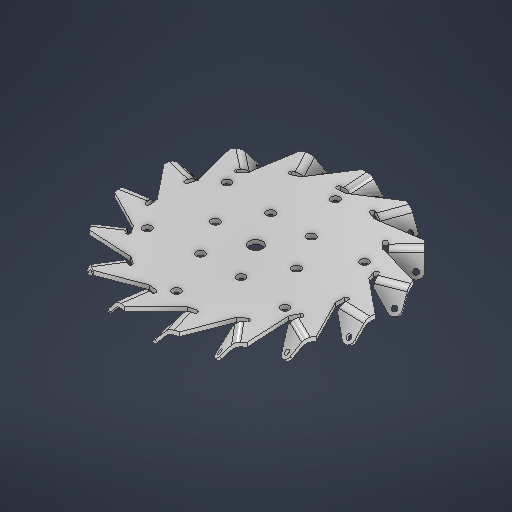
# Autodesk Inventor part: Pelk
Saved by Autodesk Inventor 2026.2 (Build 302298010, 298A)
## iProperties
Created: 2026-11-18
Part Number: Pelk
Material: Generic
Document SubType Name: Modeling
Designer: Administrator
Density: 1 g/cm^3
Appearance: Machined - Aluminum
Author: Administrator
Autodesk Inventor part; units mm, degrees
ref_plane "YZ Plane" through (0, 0, 0) normal (1, 0, 0) x (0, 1, 0)
ref_plane "XZ Plane" through (0, 0, 0) normal (0, 1, 0) x (-1, 0, 0)
sketch "Sketch1" plane through (0, 0, 0) normal (0, 1, 0) x (-1, 0, 0)
  circle A0 centre (0, 0) radius 70.5 construction
  circle A1 centre (0, 0) radius 28
  circle A2 centre (24, 0) radius 2.5
  circle A3 centre (0, -47) radius 2.5
  line L0 (-28, 0) -> (28, 0) construction
  line L1 (0, 53) -> (0, -53) construction
  circle A4 centre (12, 20.7846) radius 2.5
  circle A5 centre (40.7032, -23.5) radius 2.5
  circle A6 centre (-12, 20.7846) radius 2.5
  circle A7 centre (40.7032, 23.5) radius 2.5
  circle A8 centre (-24, 0) radius 2.5
  circle A9 centre (0, 47) radius 2.5
  circle A10 centre (-12, -20.7846) radius 2.5
  circle A11 centre (-40.7032, 23.5) radius 2.5
  circle A12 centre (12, -20.7846) radius 2.5
  circle A13 centre (-40.7032, -23.5) radius 2.5
  arc A14 (5.1152, -55.2638) -> (5.0796, -52.7716) centre (5, -54.0191) ccw
  line L2 (0, 0) -> (35.25, -61.0548) construction
  line L3 (68.9594, -14.6578) -> (52.7013, 5.6191)
  line L4 (68.9594, -14.6578) -> (67.7471, -19.5086)
  line L5 (67.7471, -19.5086) -> (53.3328, -15.3578)
  arc A15 (27.1508, -48.4054) -> (26.1046, -46.1432) centre (26.5393, -47.3152) ccw
  line L6 (0, 0) -> (57.0357, -41.4389) construction
  arc A16 (44.4917, -33.1773) -> (42.6159, -31.5363) centre (43.4897, -32.4301) ccw
  line L7 (0, 0) -> (68.9594, -14.6578) construction
  arc A17 (54.1397, -12.2126) -> (51.7585, -11.4764) centre (52.9203, -11.9375) ccw
  line L8 (0, 0) -> (68.9594, 14.6578) construction
  arc A18 (54.4263, 10.8638) -> (51.9516, 10.5679) centre (53.2005, 10.6191) ccw
  line L9 (0, 0) -> (57.0357, 41.4389) construction
  arc A19 (45.3022, 32.0618) -> (43.1618, 30.7849) centre (44.2819, 31.3397) ccw
  line L10 (0, 0) -> (35.25, 61.0548) construction
  arc A20 (28.3449, 47.716) -> (26.9089, 45.6788) centre (27.7065, 46.6413) ccw
  line L11 (0, 0) -> (7.3693, 70.1138) construction
  arc A21 (6.4866, 55.1196) -> (6.0033, 52.6745) centre (6.3405, 53.8782) ccw
  line L12 (0, 0) -> (-21.7857, 67.0495) construction
  arc A22 (-16.4934, 52.9926) -> (-15.9404, 50.5623) centre (-16.1219, 51.7991) ccw
  line L13 (0, 0) -> (-47.1737, 52.3917) construction
  arc A23 (-36.6215, 41.7027) -> (-35.1278, 39.7074) centre (-35.7967, 40.7634) ccw
  line L14 (0, 0) -> (-64.405, 28.6749) construction
  arc A24 (-50.4174, 23.202) -> (-48.2414, 21.9868) centre (-49.2819, 22.6794) ccw
  line L15 (0, 0) -> (-70.5, 0) construction
  arc A25 (-55.4957, 0.6895) -> (-53.0135, 0.4644) centre (-54.2458, 0.6739) ccw
  line L16 (0, 0) -> (-64.405, -28.6749) construction
  arc A26 (-50.9783, -21.9423) -> (-48.6191, -21.1383) centre (-49.8301, -21.4481) ccw
  line L17 (0, 0) -> (-47.1737, -52.3917) construction
  arc A27 (-37.6462, -40.78) -> (-35.8181, -39.086) centre (-36.7984, -39.8616) ccw
  line L18 (0, 0) -> (-21.7857, -67.0495) construction
  arc A28 (-17.8048, -52.5665) -> (-16.8237, -50.2753) centre (-17.4038, -51.3826) ccw
  line L19 (0, 0) -> (7.3693, -70.1138) construction
  line L20 (69.8249, 9.7332) -> (54.9685, 7.6623)
  line L21 (68.9594, 14.6578) -> (45.8595, 26.5689)
  line L22 (59.8293, 37.2921) -> (47.0997, 29.3576)
  line L23 (57.0357, 41.4389) -> (31.0882, 42.9246)
  line L24 (39.4888, 58.4028) -> (31.0869, 45.9767)
  line L25 (35.25, 61.0548) -> (10.9415, 51.8583)
  line L26 (12.3202, 69.4151) -> (9.6989, 54.646)
  line L27 (7.3693, 70.1138) -> (-11.0971, 51.8252)
  line L28 (-16.9786, 68.425) -> (-13.3661, 53.8665)
  line L29 (-21.7857, 67.0495) -> (-31.217, 42.8311)
  line L30 (-43.3417, 55.6035) -> (-34.12, 43.773)
  line L31 (-47.1737, 52.3917) -> (-45.9391, 26.4311)
  line L32 (-62.2106, 33.1677) -> (-48.9743, 26.1107)
  line L33 (-64.405, 28.6749) -> (-52.7179, 5.4609)
  line L34 (-70.3227, 4.9969) -> (-55.3604, 3.9337)
  line L35 (-70.5, 0) -> (-50.3813, -16.4536)
  line L36 (-66.2754, -24.038) -> (-52.1742, -18.9235)
  line L37 (-64.405, -28.6749) -> (-39.3334, -35.523)
  line L38 (-50.7685, -48.9164) -> (-39.9667, -38.5087)
  line L39 (-47.1737, -52.3917) -> (-21.4843, -48.4502)
  line L40 (-26.4832, -65.3367) -> (-20.8485, -51.4353)
  line L41 (-21.7857, -67.0495) -> (0.0796, -52.9999)
  line L42 (2.3812, -70.4598) -> (1.8746, -55.4683)
  line L43 (7.3693, -70.1138) -> (21.6297, -48.3855)
  line L44 (30.8339, -63.3997) -> (24.2735, -49.9104)
  line L45 (35.25, -61.0548) -> (39.4399, -35.4047)
  line L46 (53.9552, -45.3772) -> (42.4754, -35.7225)
  line L47 (57.0357, -41.4389) -> (50.4305, -16.3022)
  arc A29 (43.1618, 30.7849) -> (42.8905, 31.1617) centre (0, 0) ccw
  arc A30 (26.9089, 45.6788) -> (26.5078, 45.9128) centre (0, 0) ccw
  arc A31 (6.0033, 52.6745) -> (5.5416, 52.7251) centre (0, 0) ccw
  arc A32 (-15.9404, 50.5623) -> (-16.3827, 50.4208) centre (0, 0) ccw
  arc A33 (-35.1278, 39.7074) -> (-35.4743, 39.3982) centre (0, 0) ccw
  arc A34 (-48.2414, 21.9868) -> (-48.4321, 21.5634) centre (0, 0) ccw
  arc A35 (-53.0135, 0.4644) -> (-53.0155, 0) centre (0, 0) ccw
  arc A36 (-48.6191, -21.1383) -> (-48.4321, -21.5634) centre (0, 0) ccw
  arc A37 (-35.8181, -39.086) -> (-35.4743, -39.3982) centre (0, 0) ccw
  arc A38 (-16.8237, -50.2753) -> (-16.3827, -50.4208) centre (0, 0) ccw
  line L48 (68.9594, 14.6578) -> (69.8249, 9.7332)
  line L49 (57.0357, 41.4389) -> (59.8293, 37.2921)
  line L50 (35.25, 61.0548) -> (39.4888, 58.4028)
  line L51 (7.3693, 70.1138) -> (12.3202, 69.4151)
  line L52 (-21.7857, 67.0495) -> (-16.9786, 68.425)
  line L53 (-47.1737, 52.3917) -> (-43.3417, 55.6035)
  line L54 (-64.405, 28.6749) -> (-62.2106, 33.1677)
  line L55 (-70.5, 0) -> (-70.3227, 4.9969)
  line L56 (-64.405, -28.6749) -> (-66.2754, -24.038)
  line L57 (-47.1737, -52.3917) -> (-50.7685, -48.9164)
  line L58 (-21.7857, -67.0495) -> (-26.4832, -65.3367)
  line L59 (7.3693, -70.1138) -> (2.3812, -70.4598)
  line L60 (35.25, -61.0548) -> (30.8339, -63.3997)
  line L61 (57.0357, -41.4389) -> (53.9552, -45.3772)
  line L62 (5.0796, -52.7716) -> (0.0796, -52.9999)
  line L63 (5.1152, -55.2638) -> (1.8746, -55.4683)
  line L64 (26.1046, -46.1432) -> (21.6297, -48.3855)
  line L65 (27.1508, -48.4054) -> (24.2735, -49.9104)
  line L66 (42.6159, -31.5363) -> (39.4399, -35.4047)
  line L67 (44.4917, -33.1773) -> (42.4754, -35.7225)
  line L68 (51.7585, -11.4764) -> (50.4305, -16.3022)
  line L69 (54.1397, -12.2126) -> (53.3328, -15.3578)
  line L70 (51.9516, 10.5679) -> (52.7013, 5.6191)
  line L71 (54.4263, 10.8638) -> (54.9685, 7.6623)
  line L72 (43.1618, 30.7849) -> (45.8595, 26.5689)
  line L73 (45.3022, 32.0618) -> (47.0997, 29.3576)
  line L74 (26.9089, 45.6788) -> (31.0882, 42.9246)
  line L75 (28.3449, 47.716) -> (31.0869, 45.9767)
  line L76 (6.0033, 52.6745) -> (10.9415, 51.8583)
  line L77 (6.4866, 55.1196) -> (9.6989, 54.646)
  line L78 (-15.9404, 50.5623) -> (-11.0971, 51.8252)
  line L79 (-16.4934, 52.9926) -> (-13.3661, 53.8665)
  line L80 (-35.1278, 39.7074) -> (-31.217, 42.8311)
  line L81 (-36.6215, 41.7027) -> (-34.12, 43.773)
  line L82 (-48.2414, 21.9868) -> (-45.9391, 26.4311)
  line L83 (-50.4174, 23.202) -> (-48.9743, 26.1107)
  line L84 (-53.0135, 0.4644) -> (-52.7179, 5.4609)
  line L85 (-55.4957, 0.6895) -> (-55.3604, 3.9337)
  line L86 (-48.6191, -21.1383) -> (-50.3813, -16.4536)
  line L87 (-50.9783, -21.9423) -> (-52.1742, -18.9235)
  line L88 (-35.8181, -39.086) -> (-39.3334, -35.523)
  line L89 (-37.6462, -40.78) -> (-39.9667, -38.5087)
  line L90 (-16.8237, -50.2753) -> (-21.4843, -48.4502)
  line L91 (-17.8048, -52.5665) -> (-20.8485, -51.4353)
  circle A39 centre (0, 0) radius 4
  point P0 (19.4164, -14.1068)
  point P1 (23.4755, -4.9899)
  point P2 (23.4755, 4.9899)
  point P3 (19.4164, 14.1068)
  point P4 (12, 20.7846)
  point P5 (2.5087, 23.8685)
  point P6 (-7.4164, 22.8254)
  point P7 (-16.0591, 17.8355)
  point P8 (-21.9251, 9.7617)
  point P9 (-24, 0)
  point P10 (-21.9251, -9.7617)
  point P11 (-16.0591, -17.8355)
  point P12 (-7.4164, -22.8254)
  point P13 (2.5087, -23.8685)
  point P14 (43.2616, 30.6176)
  point P15 (27.0681, 45.5666)
  point P16 (6.1944, 52.6368)
  point P17 (-15.7505, 50.6056)
  point P18 (-34.9719, 39.8242)
  point P19 (-48.1464, 22.1569)
  point P20 (-52.9959, 0.6584)
  point P21 (-48.682, -20.9539)
  point P22 (-35.9505, -38.9431)
  point P23 (-17.0028, -50.1987)
  point P24 (26.1046, -46.1432)
  point P25 (27.1508, -48.4054)
  point P26 (42.6159, -31.5363)
  point P27 (44.4917, -33.1773)
  point P28 (51.7585, -11.4764)
  point P29 (54.1397, -12.2126)
  point P30 (54.4263, 10.8638)
  point P31 (43.1618, 30.7849)
  point P32 (45.3022, 32.0618)
  point P33 (26.9089, 45.6788)
  point P34 (28.3449, 47.716)
  point P35 (6.0033, 52.6745)
  point P36 (6.4866, 55.1196)
  point P37 (-15.9404, 50.5623)
  point P38 (-16.4934, 52.9926)
  point P39 (-35.1278, 39.7074)
  point P40 (-36.6215, 41.7027)
  point P41 (-48.2414, 21.9868)
  point P42 (-50.4174, 23.202)
  point P43 (-52.7179, 5.4609)
  point P44 (-53.0135, 0.4644)
  point P45 (-55.4957, 0.6895)
  point P46 (-50.9783, -21.9423)
  point P47 (-37.6462, -40.78)
  point P48 (-17.8048, -52.5665)
  dimension "d3" = 56
  dimension "d0" = 141
  dimension "d4" = 5
  dimension "d5" = 5
  dimension "d6" = 4
  dimension "d7" = 6
  dimension "d10" = 360
  dimension "d12" = 5
  dimension "d19" = 5
  dimension "d22" = 360
  dimension "d26" = 360
  dimension "d30" = 360
  dimension "d34" = 5
  dimension "d35" = 1.25
  dimension "d38" = 360
  dimension "d57" = 8
  constraints: 184 end point, 53 point on circle, 41 point on line, 39 centre point, 5 coincident, 2 midpoint, 1 horizontal, 1 horizontal alignment, 1 perpendicular, 389 other
  measures "d0" diameter of A0
  measures "d4" diameter of A2
  measures "d5" diameter of A3
  measures "d6" distance of L0.end A2.centre
  measures "d7" distance of L1.end A3.centre
  measures "d12" horizontal distance of A3.centre A14.centre
  measures "d19" distance of L3.start L4.end
  measures "d34" horizontal distance of L62.start L41.end
  measures "d35" radius of A14
  measures "d57" diameter of A39
extrude "Extrusion1" add sketch "Sketch1" along normal blind 2.5 contours A1 | A14 L62 L41 L58 L40 L91 A28 L90 L39 L57 L38 L89 A27 L88 L37 L56 L36 L87 A26 L86 L35 L55 L34 L85 A25 L84 L33 L54 L32 L83 A24 L82 L31 L53 L30 L81 A23 L80 L29 L52 L28 L79 A22 L78 L27 L51 L26 L77 A21 L76 L25 L50 L24 L75 A20 L74 L23 L49 L22 L73 A19 L72 L21 L48 L20 L71 A18 L70 L3 L4 L5 L69 A17 L68 L47 L61 L46 L67 A16 L66 L45 L60 L44 L65 A15 L64 L43 L59 L42 L63
sketch "Sketch2" plane through (21.7857, 0, -67.0495) normal (0.342548, 0, -0.9395003) x (-0.9395003, 0, -0.342548)
  line L0 (-5, 0) -> (0, 0) projected
  line L1 (0, 0) -> (0, 2.5) projected
  line L2 (-5, 2.5) -> (0, 2.5) projected
  line L3 (-5, 0) -> (-5, 2.5) projected
  line L4 (-5, 2.5) -> (-13.9445, -8.1596)
  line L5 (-5, 0) -> (-12.7135, -9.1925)
  line L6 (-5, 2.5) -> (-17.5199, 2.5) construction
  line L7 (-13.9445, -8.1596) -> (-12.7135, -9.1925)
  dimension "d40" = 12
  dimension "d41" = 50
  constraints: 8 end point, 1 horizontal, 1 parallel, 1 perpendicular
  measures "d40" distance of L0.start L5.end
  measures "d41" angle of L4 L6
extrude "Extrusion2" add sketch "Sketch2" against normal blind 15
fillet "Fillet1" radius 5 2 edges at (23.9141, 2.5, -58.2905) (23.9141, 0, -58.2905)
chamfer "Chamfer1" distance 10 angle 45 1 edges at (29.17, -8.6761, -48.3912)
fillet "Fillet2" radius 3.5 2 edges at (34.3083, -8.6761, -62.4837) (32.5955, -8.6761, -57.7862)
sketch "Sketch3" plane through (22.753, 0.7139, -50.7309) normal (0.719699, 0.6427876, 0.262407) x (0.6038992, -0.7660444, 0.2201856)
  arc A0 (10.5584, 8.9749) -> (11.5836, 11.4497) centre (8.0836, 11.4497) ccw projected
  line L0 (11.5836, 11.5) -> (11.5836, 11.4497) projected
  arc A1 (11.5836, 11.5) -> (8.0836, 15) centre (8.0836, 11.5) ccw projected
  line L1 (0, 15) -> (8.0836, 15) projected
  line L2 (0, 0) -> (0, 15) projected
  line L3 (1.5836, 0) -> (0, 0) projected
  line L4 (10.5584, 8.9749) -> (1.5836, 0) projected
  circle A2 centre (8.0836, 11.4749) radius 1.5
  point P0 (-2.0234, -55.4557)
  dimension "d53" = 3
  dimension "d54" = 0.0251
  constraints: 1 centre point
  measures "d53" diameter of A2
  measures "d54" distance of A1.centre A2.centre
extrude "Extrusion3" cut sketch "Sketch3" against normal blind 2 contours A2
pattern_circular "Circular Pattern2" count 15 over 360 about axis through (0, 0, 0) along (0, 1, 0) of "Extrusion2", "Fillet1", "Chamfer1", "Fillet2", "Extrusion3"
ref_plane "Work Plane1" through (0, -20.5, 0) normal (0, 1, 0) x (1, 0, 0)
body "Solid1"
